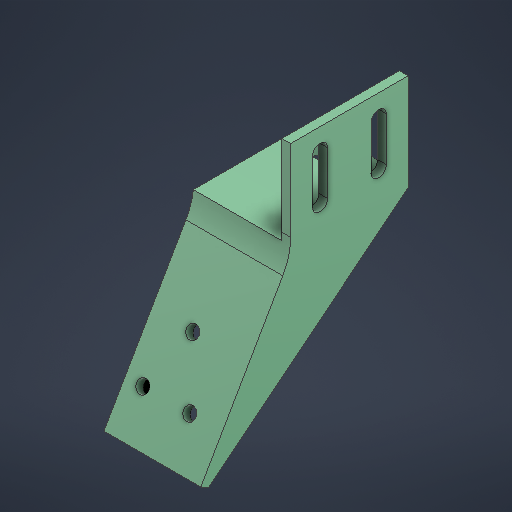
# Autodesk Inventor part: 1_1_7_1_fixation_gauche
Saved by Autodesk Inventor 2026 (Build 300175000, 175)
## iProperties
Created: 2025-05-11
Part Number: 1_1_7_1_fixation_gauche
Material: Generic
Document SubType Name: Modeling
Designer: remg9
Density: 1 g/cm^3
Appearance: Default
Author: remg9
Autodesk Inventor part; units mm, degrees
ref_plane "YZ Plane" through (0, 0, 0) normal (1, 0, 0) x (0, 1, 0)
ref_plane "XZ Plane" through (0, 0, 0) normal (0, 1, 0) x (-1, 0, 0)
ref_plane "XY Plane" through (0, 0, 0) normal (0, 0, 1) x (1, 0, 0)
sketch "Sketch1" plane through (0, 0, 0) normal (0, 1, 0) x (-1, 0, 0)
  line L0 (-16.5, 20) -> (16.5, 20)
  line L1 (16.5, 20) -> (16.5, -20)
  line L2 (16.5, -20) -> (-16.5, -20)
  line L3 (-16.5, -20) -> (-16.5, 20)
  line L4 (-16.5, 20) -> (16.5, -20) construction
  line L5 (16.5, 20) -> (-16.5, -20) construction
  point P0 (0, 0)
  dimension "d0" = 33
  dimension "d1" = 40
  constraints: 12 end point, 2 midpoint, 2 parallel, 1 horizontal, 1 perpendicular
  measures "d0" distance of L1.end L2.end
  measures "d1" distance of L2.end L0.start
extrude "Extrusion1" add sketch "Sketch1" along normal blind 3
sketch "Sketch2" plane through (0, 3, 0) normal (0, 1, 0) x (1, 0, 0)
  line L0 (16.5, 20) -> (-16.5, 20) projected
  line L1 (16.5, 20) -> (13.5, 20)
  line L2 (13.5, 20) -> (13.5, -20)
  line L3 (13.5, -20) -> (16.5, -20)
  line L4 (16.5, -20) -> (16.5, 20)
  line L5 (-16.5, -20) -> (16.5, -20) projected
  point P0 (0, 0)
  dimension "d4" = 3
  constraints: 8 end point, 2 parallel, 1 collinear, 1 horizontal, 1 perpendicular
  measures "d4" distance between parallel lines of L4 L2
extrude "Extrusion2" add sketch "Sketch2" along normal blind 30
sketch "Sketch3" plane through (0, 0, 0) normal (1, 0, 0) x (0, 1, 0)
  line L0 (0, 20) -> (0, -20) projected
  line L1 (0, 20) -> (-53, 50.5996)
  line L2 (-53, 50.5996) -> (-54.5, 48.0015)
  line L3 (-54.5, 48.0015) -> (0, -20)
  line L4 (0, -20) -> (0, 20)
  line L5 (0, 20) -> (33, 20) projected
  point P0 (0, 0)
  dimension "d8" = 150
  dimension "d10" = 3
  dimension "d11" = 53
  constraints: 8 end point, 2 point on line, 1 perpendicular
  measures "d8" angle of L5 L1
  measures "d10" distance of L1.end L2.end
  measures "d11" distance from line of L0 L1.end
extrude "Extrusion3" add sketch "Sketch3" along normal mid plane 33
sketch "Sketch4" plane through (0, 0, 0) normal (1, 0, 0) x (0, 1, 0)
  line L0 (-54.5, 48.0015) -> (0, -20) projected
  line L1 (0, -20) -> (0, 16.5359)
  line L2 (0, 16.5359) -> (-54.5, 48.0015)
  line L3 (-54.5, 48.0015) -> (0, -20)
  line L4 (-53, 50.5996) -> (0, 20) projected
  point P0 (0, 0)
  constraints: 6 end point, 1 parallel, 1 vertical
extrude "Extrusion4" cut sketch "Sketch4" along normal mid plane 27
fillet "Fillet1" radius 40 1 edges at (0, 0, 16.5359)
fillet "Fillet2" radius 20 1 edges at (0, 0, 20)
fillet "Fillet3" radius 4 3 edges at (13.5, 0, -13.2791) (13.5, -37.25, 38.0422) (13.5, -5.359, 13.4419)
sketch "Sketch6" plane through (-13.5, 0, -20) normal (0, -1, 0) x (1, 0, 0)
  line L0 (17, 7.5) -> (7, 7.5) construction
  line L1 (0, 13.4419) -> (23, 13.4419) projected
  line L2 (17, 10.1) -> (7, 10.1)
  line L3 (7, 4.9) -> (17, 4.9)
  arc A0 (17, 4.9) -> (17, 10.1) centre (17, 7.5) ccw
  arc A1 (7, 10.1) -> (7, 4.9) centre (7, 7.5) ccw
  line L4 (-3, 0) -> (-3, 68.0015) projected
  line L5 (23, 0) -> (0, 0) projected
  point P0 (13.5, 20)
  point P1 (12, 7.5)
  dimension "d31" = 5.2
  dimension "d32" = 15
  dimension "d33" = 10
  dimension "d34" = 7.5
  constraints: 8 end point, 4 point on circle, 4 tangent, 2 centre point, 2 parallel, 1 midpoint
  measures "d31" distance between parallel lines of L3 L2
  measures "d32" distance from line of L4 point (12, 7.5)
  measures "d33" distance of L3.start L3.end
  measures "d34" distance from line of L5 point (12, 7.5)
extrude "Extrusion5" cut sketch "Sketch6" against normal through all
sketch "Sketch7" plane through (16.5, 33, 20) normal (1, 0, 0) x (0, 0, -1)
  line L0 (10, -7.5) -> (10, -22.5) construction
  line L1 (7.4, -7.5) -> (7.4, -22.5)
  line L2 (12.6, -22.5) -> (12.6, -7.5)
  arc A0 (12.6, -7.5) -> (7.4, -7.5) centre (10, -7.5) ccw
  arc A1 (7.4, -22.5) -> (12.6, -22.5) centre (10, -22.5) ccw
  line L3 (20, 2.8427) -> (20, -40.0006) construction
  line L4 (40, -33) -> (40, 0) construction
  line L5 (0, -27.641) -> (0, 0) construction
  line L6 (0, 0) -> (40, 0) construction
  line L7 (30, -7.5) -> (30, -22.5) construction
  line L8 (32.6, -7.5) -> (32.6, -22.5)
  line L9 (27.4, -22.5) -> (27.4, -7.5)
  arc A2 (32.6, -7.5) -> (27.4, -7.5) centre (30, -7.5) ccw
  arc A3 (27.4, -22.5) -> (32.6, -22.5) centre (30, -22.5) ccw
  line L10 (40, -27.641) -> (40, 0) construction
  point P0 (20, -33)
  point P1 (10, -15)
  point P2 (30, -15)
  dimension "d37" = 20
  dimension "d38" = 5.2
  dimension "d39" = 15
  dimension "d40" = 10
  dimension "d41" = 15
  constraints: 20 end point, 8 point on circle, 8 symmetric about line, 4 centre point, 4 tangent, 2 vertical, 1 midpoint, 1 parallel, 2 other
  measures "d37" distance between parallel lines of L4 L3
  measures "d38" distance between parallel lines of L1 L2
  measures "d39" distance of L1.start L1.end
  measures "d40" distance from line of L5 point (10, -15)
  measures "d41" distance from line of L6 point (10, -15)
extrude "Extrusion6" cut sketch "Sketch7" against normal through all
sketch "Sketch5" plane through (-16.5, 0, 20) normal (0, 0.5, 0.866) x (1, 0, 0)
  line L0 (6, -46.6991) -> (22, -46.6991) construction
  line L1 (0, -61.1991) -> (33, -61.1991) construction
  line L2 (0, -61.1991) -> (0, 0) construction
  point P0 (16.5, 10)
  point P1 (14, -28.6991)
  dimension "d16" = 14.5
  dimension "d17" = 18
  dimension "d18" = 6
  dimension "d19" = 14
  dimension "d20" = 16
  constraints: 2 end point, 1 coincident, 1 horizontal
  measures "d16" distance between parallel lines of L1 L0
  measures "d17" distance from line of L0 point (14, -28.699)
  measures "d18" distance from line of L2 L0.start
  measures "d19" distance from line of L2 point (14, -28.699)
  measures "d20" distance of L0.start point (22, -46.699)
hole "Hole1" at (-10.5, -40.4426, 43.3496) at (-2.5, -24.8542, 34.3496) at (5.5, -40.4426, 43.3496) direction (0, -0.5, -0.866) diameter 4.3 end through all
body "Solid1"
